Autodesk Fusion 360 part; units mm, degrees
(part 2 of 7)
sketch "Stack support spoke (5)" plane through (0, 0, -6) normal (0, 0, 1) x (1, 0, 0) in component "CORE | PowerShelf"
  line L0 (25.9628, -19.0311) -> (26.8069, -19.3807)
  line L1 (26.8069, -19.3807) -> (27.7128, -19.5)
  line L2 (27.7128, -19.5) -> (28.6187, -19.3807)
  line L3 (28.6187, -19.3807) -> (29.4628, -19.0311)
  line L4 (29.4628, -19.0311) -> (30.1877, -18.4749)
  line L5 (30.1877, -18.4749) -> (30.7439, -17.75)
  line L6 (30.7439, -17.75) -> (31.0936, -16.9059)
  line L7 (31.0936, -16.9059) -> (31.2128, -16)
  line L8 (31.2128, -16) -> (31.0936, -15.0941)
  line L9 (31.0936, -15.0941) -> (30.7439, -14.25)
  line L10 (30.7439, -14.25) -> (30.1877, -13.5251)
  line L11 (30.1877, -13.5251) -> (29.4628, -12.9689)
  line L12 (29.4628, -12.9689) -> (1.75, 3.0311)
  line L13 (1.75, 3.0311) -> (0.9059, 3.3807)
  line L14 (0.9059, 3.3807) -> (0, 3.5)
  line L15 (0, 3.5) -> (-0.9059, 3.3807)
  line L16 (-0.9059, 3.3807) -> (-1.75, 3.0311)
  line L17 (-1.75, 3.0311) -> (-2.4749, 2.4749)
  line L18 (-2.4749, 2.4749) -> (-3.0311, 1.75)
  line L19 (-3.0311, 1.75) -> (-3.3807, 0.9059)
  line L20 (-3.3807, 0.9059) -> (-3.5, 0)
  line L21 (-3.5, 0) -> (-3.3807, -0.9059)
  line L22 (-3.3807, -0.9059) -> (-3.0311, -1.75)
  line L23 (-3.0311, -1.75) -> (-2.4749, -2.4749)
  line L24 (-2.4749, -2.4749) -> (-1.75, -3.0311)
  line L25 (-1.75, -3.0311) -> (25.9628, -19.0311)
extrude "Stack support spoke (6)" add sketch "Stack support spoke (5)" along normal blind 3 bodies 3 in component "CORE | PowerShelf"
ref_plane "WorkPlane8" through (0, 0, -6) normal (0, 0, 1) x (1, 0, 0) in component "CORE | PowerShelf"
sketch "Cooling and M3 stack through holes" plane through (0, 0, -6) normal (0, 0, 1) x (1, 0, 0) in component "CORE | PowerShelf"
  line L0 (7, -16.4) -> (7.3623, -16.3523)
  line L1 (7.3623, -16.3523) -> (7.7, -16.2124)
  line L2 (7.7, -16.2124) -> (7.9899, -15.9899)
  line L3 (7.9899, -15.9899) -> (8.2124, -15.7)
  line L4 (8.2124, -15.7) -> (8.3523, -15.3623)
  line L5 (8.3523, -15.3623) -> (8.4, -15)
  line L6 (8.4, -15) -> (8.3523, -14.6377)
  line L7 (8.3523, -14.6377) -> (8.2124, -14.3)
  line L8 (8.2124, -14.3) -> (7.9899, -14.0101)
  line L9 (7.9899, -14.0101) -> (7.7, -13.7876)
  line L10 (7.7, -13.7876) -> (7.3623, -13.6477)
  line L11 (7.3623, -13.6477) -> (7, -13.6)
  line L12 (7, -13.6) -> (-7, -13.6)
  line L13 (-7, -13.6) -> (-7.3623, -13.6477)
  line L14 (-7.3623, -13.6477) -> (-7.7, -13.7876)
  line L15 (-7.7, -13.7876) -> (-7.9899, -14.0101)
  line L16 (-7.9899, -14.0101) -> (-8.2124, -14.3)
  line L17 (-8.2124, -14.3) -> (-8.3523, -14.6377)
  line L18 (-8.3523, -14.6377) -> (-8.4, -15)
  line L19 (-8.4, -15) -> (-8.3523, -15.3623)
  line L20 (-8.3523, -15.3623) -> (-8.2124, -15.7)
  line L21 (-8.2124, -15.7) -> (-7.9899, -15.9899)
  line L22 (-7.9899, -15.9899) -> (-7.7, -16.2124)
  line L23 (-7.7, -16.2124) -> (-7.3623, -16.3523)
  line L24 (-7.3623, -16.3523) -> (-7, -16.4)
  line L25 (-7, -16.4) -> (7, -16.4)
  line L26 (7, -9.4) -> (7.3623, -9.3523)
  line L27 (7.3623, -9.3523) -> (7.7, -9.2124)
  line L28 (7.7, -9.2124) -> (7.9899, -8.9899)
  line L29 (7.9899, -8.9899) -> (8.2124, -8.7)
  line L30 (8.2124, -8.7) -> (8.3523, -8.3623)
  line L31 (8.3523, -8.3623) -> (8.4, -8)
  line L32 (8.4, -8) -> (8.3523, -7.6377)
  line L33 (8.3523, -7.6377) -> (8.2124, -7.3)
  line L34 (8.2124, -7.3) -> (7.9899, -7.0101)
  line L35 (7.9899, -7.0101) -> (7.7, -6.7876)
  line L36 (7.7, -6.7876) -> (7.3623, -6.6477)
  line L37 (7.3623, -6.6477) -> (7, -6.6)
  line L38 (7, -6.6) -> (-7, -6.6)
  line L39 (-7, -6.6) -> (-7.3623, -6.6477)
  line L40 (-7.3623, -6.6477) -> (-7.7, -6.7876)
  line L41 (-7.7, -6.7876) -> (-7.9899, -7.0101)
  line L42 (-7.9899, -7.0101) -> (-8.2124, -7.3)
  line L43 (-8.2124, -7.3) -> (-8.3523, -7.6377)
  line L44 (-8.3523, -7.6377) -> (-8.4, -8)
  line L45 (-8.4, -8) -> (-8.3523, -8.3623)
  line L46 (-8.3523, -8.3623) -> (-8.2124, -8.7)
  line L47 (-8.2124, -8.7) -> (-7.9899, -8.9899)
  line L48 (-7.9899, -8.9899) -> (-7.7, -9.2124)
  line L49 (-7.7, -9.2124) -> (-7.3623, -9.3523)
  line L50 (-7.3623, -9.3523) -> (-7, -9.4)
  line L51 (-7, -9.4) -> (7, -9.4)
  line L52 (7, -1.4) -> (7.3623, -1.3523)
  line L53 (7.3623, -1.3523) -> (7.7, -1.2124)
  line L54 (7.7, -1.2124) -> (7.9899, -0.9899)
  line L55 (7.9899, -0.9899) -> (8.2124, -0.7)
  line L56 (8.2124, -0.7) -> (8.3523, -0.3623)
  line L57 (8.3523, -0.3623) -> (8.4, 0)
  line L58 (8.4, 0) -> (8.3523, 0.3623)
  line L59 (8.3523, 0.3623) -> (8.2124, 0.7)
  line L60 (8.2124, 0.7) -> (7.9899, 0.9899)
  line L61 (7.9899, 0.9899) -> (7.7, 1.2124)
  line L62 (7.7, 1.2124) -> (7.3623, 1.3523)
  line L63 (7.3623, 1.3523) -> (7, 1.4)
  line L64 (7, 1.4) -> (-7, 1.4)
  line L65 (-7, 1.4) -> (-7.3623, 1.3523)
  line L66 (-7.3623, 1.3523) -> (-7.7, 1.2124)
  line L67 (-7.7, 1.2124) -> (-7.9899, 0.9899)
  line L68 (-7.9899, 0.9899) -> (-8.2124, 0.7)
  line L69 (-8.2124, 0.7) -> (-8.3523, 0.3623)
  line L70 (-8.3523, 0.3623) -> (-8.4, 0)
  line L71 (-8.4, 0) -> (-8.3523, -0.3623)
  line L72 (-8.3523, -0.3623) -> (-8.2124, -0.7)
  line L73 (-8.2124, -0.7) -> (-7.9899, -0.9899)
  line L74 (-7.9899, -0.9899) -> (-7.7, -1.2124)
  line L75 (-7.7, -1.2124) -> (-7.3623, -1.3523)
  line L76 (-7.3623, -1.3523) -> (-7, -1.4)
  line L77 (-7, -1.4) -> (7, -1.4)
  line L78 (7, 6.6) -> (7.3623, 6.6477)
  line L79 (7.3623, 6.6477) -> (7.7, 6.7876)
  line L80 (7.7, 6.7876) -> (7.9899, 7.0101)
  line L81 (7.9899, 7.0101) -> (8.2124, 7.3)
  line L82 (8.2124, 7.3) -> (8.3523, 7.6377)
  line L83 (8.3523, 7.6377) -> (8.4, 8)
  line L84 (8.4, 8) -> (8.3523, 8.3623)
  line L85 (8.3523, 8.3623) -> (8.2124, 8.7)
  line L86 (8.2124, 8.7) -> (7.9899, 8.9899)
  line L87 (7.9899, 8.9899) -> (7.7, 9.2124)
  line L88 (7.7, 9.2124) -> (7.3623, 9.3523)
  line L89 (7.3623, 9.3523) -> (7, 9.4)
  line L90 (7, 9.4) -> (-7, 9.4)
  line L91 (-7, 9.4) -> (-7.3623, 9.3523)
  line L92 (-7.3623, 9.3523) -> (-7.7, 9.2124)
  line L93 (-7.7, 9.2124) -> (-7.9899, 8.9899)
  line L94 (-7.9899, 8.9899) -> (-8.2124, 8.7)
  line L95 (-8.2124, 8.7) -> (-8.3523, 8.3623)
  line L96 (-8.3523, 8.3623) -> (-8.4, 8)
  line L97 (-8.4, 8) -> (-8.3523, 7.6377)
  line L98 (-8.3523, 7.6377) -> (-8.2124, 7.3)
  line L99 (-8.2124, 7.3) -> (-7.9899, 7.0101)
  line L100 (-7.9899, 7.0101) -> (-7.7, 6.7876)
  line L101 (-7.7, 6.7876) -> (-7.3623, 6.6477)
  line L102 (-7.3623, 6.6477) -> (-7, 6.6)
  line L103 (-7, 6.6) -> (7, 6.6)
  line L104 (7, 13.6) -> (7.3623, 13.6477)
  line L105 (7.3623, 13.6477) -> (7.7, 13.7876)
  line L106 (7.7, 13.7876) -> (7.9899, 14.0101)
  line L107 (7.9899, 14.0101) -> (8.2124, 14.3)
  line L108 (8.2124, 14.3) -> (8.3523, 14.6377)
  line L109 (8.3523, 14.6377) -> (8.4, 15)
  line L110 (8.4, 15) -> (8.3523, 15.3623)
  line L111 (8.3523, 15.3623) -> (8.2124, 15.7)
  line L112 (8.2124, 15.7) -> (7.9899, 15.9899)
  line L113 (7.9899, 15.9899) -> (7.7, 16.2124)
  line L114 (7.7, 16.2124) -> (7.3623, 16.3523)
  line L115 (7.3623, 16.3523) -> (7, 16.4)
  line L116 (7, 16.4) -> (-7, 16.4)
  line L117 (-7, 16.4) -> (-7.3623, 16.3523)
  line L118 (-7.3623, 16.3523) -> (-7.7, 16.2124)
  line L119 (-7.7, 16.2124) -> (-7.9899, 15.9899)
  line L120 (-7.9899, 15.9899) -> (-8.2124, 15.7)
  line L121 (-8.2124, 15.7) -> (-8.3523, 15.3623)
  line L122 (-8.3523, 15.3623) -> (-8.4, 15)
  line L123 (-8.4, 15) -> (-8.3523, 14.6377)
  line L124 (-8.3523, 14.6377) -> (-8.2124, 14.3)
  line L125 (-8.2124, 14.3) -> (-7.9899, 14.0101)
  line L126 (-7.9899, 14.0101) -> (-7.7, 13.7876)
  line L127 (-7.7, 13.7876) -> (-7.3623, 13.6477)
  line L128 (-7.3623, 13.6477) -> (-7, 13.6)
  line L129 (-7, 13.6) -> (7, 13.6)
  circle A0 centre (27.7128, 16) radius 1.7
  circle A1 centre (0, 32) radius 1.7
  circle A2 centre (-27.7128, 16) radius 1.7
  circle A3 centre (-27.7128, -16) radius 1.7
  circle A4 centre (0, -32) radius 1.7
  circle A5 centre (27.7128, -16) radius 1.7
extrude "Cooling and M3 stack through holes (1)" cut sketch "Cooling and M3 stack through holes" along normal blind 3 bodies 3 in component "CORE | PowerShelf"
ref_plane "WorkPlane9" through (0, 0, -3) normal (0, 0, 1) x (1, 0, 0) in component "CORE | PowerShelf"
sketch "M2 regulator standoff" plane through (0, 0, -3) normal (0, 0, 1) x (1, 0, 0) in component "CORE | PowerShelf"
  circle A0 centre (-13.716, -19.431) radius 2.8
extrude "M2 regulator standoff (1)" add sketch "M2 regulator standoff" along normal blind 2 bodies 3 in component "CORE | PowerShelf"
ref_plane "WorkPlane10" through (0, 0, -3) normal (0, 0, 1) x (1, 0, 0) in component "CORE | PowerShelf"
sketch "M2 regulator standoff (1)" plane through (0, 0, -3) normal (0, 0, 1) x (1, 0, 0) in component "CORE | PowerShelf"
  circle A0 centre (11.684, -19.431) radius 2.8
extrude "M2 regulator standoff (2)" add sketch "M2 regulator standoff (1)" along normal blind 2 bodies 3 in component "CORE | PowerShelf"
ref_plane "WorkPlane11" through (0, 0, -3) normal (0, 0, 1) x (1, 0, 0) in component "CORE | PowerShelf"
sketch "M2 regulator standoff (2)" plane through (0, 0, -3) normal (0, 0, 1) x (1, 0, 0) in component "CORE | PowerShelf"
  circle A0 centre (-13.716, 19.431) radius 2.8
extrude "M2 regulator standoff (3)" add sketch "M2 regulator standoff (2)" along normal blind 2 bodies 3 in component "CORE | PowerShelf"
ref_plane "WorkPlane12" through (0, 0, -3) normal (0, 0, 1) x (1, 0, 0) in component "CORE | PowerShelf"
sketch "M2 regulator standoff (3)" plane through (0, 0, -3) normal (0, 0, 1) x (1, 0, 0) in component "CORE | PowerShelf"
  circle A0 centre (11.684, 19.431) radius 2.8
extrude "M2 regulator standoff (4)" add sketch "M2 regulator standoff (3)" along normal blind 2 bodies 3 in component "CORE | PowerShelf"
ref_plane "WorkPlane13" through (0, 0, -6) normal (0, 0, 1) x (1, 0, 0) in component "CORE | PowerShelf"
sketch "Pololu D42 exact M2 pattern" plane through (0, 0, -6) normal (0, 0, 1) x (1, 0, 0) in component "CORE | PowerShelf"
  circle A0 centre (-13.716, -19.431) radius 1.2
  circle A1 centre (11.684, -19.431) radius 1.2
  circle A2 centre (-13.716, 19.431) radius 1.2
  circle A3 centre (11.684, 19.431) radius 1.2
extrude "Pololu D42 exact M2 pattern (1)" cut sketch "Pololu D42 exact M2 pattern" along normal blind 5 bodies 3 in component "CORE | PowerShelf"
ref_plane "WorkPlane1" through (0, 0, 12) normal (0, 0, 1) x (1, 0, 0) in component "CORE | ElectronicsDeck"
sketch "PCA open frame" plane through (0, 0, 12) normal (0, 0, 1) x (1, 0, 0) in component "CORE | ElectronicsDeck"
  line L0 (43, 0) -> (42.6321, 5.7432)
  line L1 (42.6321, 5.7432) -> (41.5348, 11.388)
  line L2 (41.5348, 11.388) -> (39.7268, 16.8381)
  line L3 (39.7268, 16.8381) -> (37.2391, 22)
  line L4 (37.2391, 22) -> (34.1142, 26.7855)
  line L5 (34.1142, 26.7855) -> (30.4056, 31.1127)
  line L6 (30.4056, 31.1127) -> (26.1767, 34.9075)
  line L7 (26.1767, 34.9075) -> (21.5, 38.1051)
  line L8 (21.5, 38.1051) -> (16.4554, 40.6507)
  line L9 (16.4554, 40.6507) -> (11.1292, 42.5007)
  line L10 (11.1292, 42.5007) -> (5.6126, 43.6236)
  line L11 (5.6126, 43.6236) -> (0, 44)
  line L12 (0, 44) -> (-5.6126, 43.6236)
  line L13 (-5.6126, 43.6236) -> (-11.1292, 42.5007)
  line L14 (-11.1292, 42.5007) -> (-16.4554, 40.6507)
  line L15 (-16.4554, 40.6507) -> (-21.5, 38.1051)
  line L16 (-21.5, 38.1051) -> (-26.1767, 34.9075)
  line L17 (-26.1767, 34.9075) -> (-30.4056, 31.1127)
  line L18 (-30.4056, 31.1127) -> (-34.1142, 26.7855)
  line L19 (-34.1142, 26.7855) -> (-37.2391, 22)
  line L20 (-37.2391, 22) -> (-39.7268, 16.8381)
  line L21 (-39.7268, 16.8381) -> (-41.5348, 11.388)
  line L22 (-41.5348, 11.388) -> (-42.6321, 5.7432)
  line L23 (-42.6321, 5.7432) -> (-43, 0)
  line L24 (-43, 0) -> (-42.6321, -5.7432)
  line L25 (-42.6321, -5.7432) -> (-41.5348, -11.388)
  line L26 (-41.5348, -11.388) -> (-39.7268, -16.8381)
  line L27 (-39.7268, -16.8381) -> (-37.2391, -22)
  line L28 (-37.2391, -22) -> (-34.1142, -26.7855)
  line L29 (-34.1142, -26.7855) -> (-30.4056, -31.1127)
  line L30 (-30.4056, -31.1127) -> (-26.1767, -34.9075)
  line L31 (-26.1767, -34.9075) -> (-21.5, -38.1051)
  line L32 (-21.5, -38.1051) -> (-16.4554, -40.6507)
  line L33 (-16.4554, -40.6507) -> (-11.1292, -42.5007)
  line L34 (-11.1292, -42.5007) -> (-5.6126, -43.6236)
  line L35 (-5.6126, -43.6236) -> (0, -44)
  line L36 (0, -44) -> (5.6126, -43.6236)
  line L37 (5.6126, -43.6236) -> (11.1292, -42.5007)
  line L38 (11.1292, -42.5007) -> (16.4554, -40.6507)
  line L39 (16.4554, -40.6507) -> (21.5, -38.1051)
  line L40 (21.5, -38.1051) -> (26.1767, -34.9075)
  line L41 (26.1767, -34.9075) -> (30.4056, -31.1127)
  line L42 (30.4056, -31.1127) -> (34.1142, -26.7855)
  line L43 (34.1142, -26.7855) -> (37.2391, -22)
  line L44 (37.2391, -22) -> (39.7268, -16.8381)
  line L45 (39.7268, -16.8381) -> (41.5348, -11.388)
  line L46 (41.5348, -11.388) -> (42.6321, -5.7432)
  line L47 (42.6321, -5.7432) -> (43, 0)
extrude "PCA open frame (1)" add sketch "PCA open frame" along normal blind 3 separate body makes body 4 in component "CORE | ElectronicsDeck"
ref_plane "WorkPlane2" through (0, 0, 12) normal (0, 0, 1) x (1, 0, 0) in component "CORE | ElectronicsDeck"
sketch "Core open cooling aperture" plane through (0, 0, 12) normal (0, 0, 1) x (1, 0, 0) in component "CORE | ElectronicsDeck"
  line L0 (35, 0) -> (34.7006, 4.6989)
  line L1 (34.7006, 4.6989) -> (33.8074, 9.3175)
  line L2 (33.8074, 9.3175) -> (32.3358, 13.7766)
  line L3 (32.3358, 13.7766) -> (30.3109, 18)
  line L4 (30.3109, 18) -> (27.7674, 21.9154)
  line L5 (27.7674, 21.9154) -> (24.7487, 25.4558)
  line L6 (24.7487, 25.4558) -> (21.3067, 28.5607)
  line L7 (21.3067, 28.5607) -> (17.5, 31.1769)
  line L8 (17.5, 31.1769) -> (13.3939, 33.2597)
  line L9 (13.3939, 33.2597) -> (9.0587, 34.7733)
  line L10 (9.0587, 34.7733) -> (4.5684, 35.692)
  line L11 (4.5684, 35.692) -> (0, 36)
  line L12 (0, 36) -> (-4.5684, 35.692)
  line L13 (-4.5684, 35.692) -> (-9.0587, 34.7733)
  line L14 (-9.0587, 34.7733) -> (-13.3939, 33.2597)
  line L15 (-13.3939, 33.2597) -> (-17.5, 31.1769)
  line L16 (-17.5, 31.1769) -> (-21.3067, 28.5607)
  line L17 (-21.3067, 28.5607) -> (-24.7487, 25.4558)
  line L18 (-24.7487, 25.4558) -> (-27.7674, 21.9154)
  line L19 (-27.7674, 21.9154) -> (-30.3109, 18)
  line L20 (-30.3109, 18) -> (-32.3358, 13.7766)
  line L21 (-32.3358, 13.7766) -> (-33.8074, 9.3175)
  line L22 (-33.8074, 9.3175) -> (-34.7006, 4.6989)
  line L23 (-34.7006, 4.6989) -> (-35, 0)
  line L24 (-35, 0) -> (-34.7006, -4.6989)
  line L25 (-34.7006, -4.6989) -> (-33.8074, -9.3175)
  line L26 (-33.8074, -9.3175) -> (-32.3358, -13.7766)
  line L27 (-32.3358, -13.7766) -> (-30.3109, -18)
  line L28 (-30.3109, -18) -> (-27.7674, -21.9154)
  line L29 (-27.7674, -21.9154) -> (-24.7487, -25.4558)
  line L30 (-24.7487, -25.4558) -> (-21.3067, -28.5607)
  line L31 (-21.3067, -28.5607) -> (-17.5, -31.1769)
  line L32 (-17.5, -31.1769) -> (-13.3939, -33.2597)
  line L33 (-13.3939, -33.2597) -> (-9.0587, -34.7733)
  line L34 (-9.0587, -34.7733) -> (-4.5684, -35.692)
  line L35 (-4.5684, -35.692) -> (0, -36)
  line L36 (0, -36) -> (4.5684, -35.692)
  line L37 (4.5684, -35.692) -> (9.0587, -34.7733)
  line L38 (9.0587, -34.7733) -> (13.3939, -33.2597)
  line L39 (13.3939, -33.2597) -> (17.5, -31.1769)
  line L40 (17.5, -31.1769) -> (21.3067, -28.5607)
  line L41 (21.3067, -28.5607) -> (24.7487, -25.4558)
  line L42 (24.7487, -25.4558) -> (27.7674, -21.9154)
  line L43 (27.7674, -21.9154) -> (30.3109, -18)
  line L44 (30.3109, -18) -> (32.3358, -13.7766)
  line L45 (32.3358, -13.7766) -> (33.8074, -9.3175)
  line L46 (33.8074, -9.3175) -> (34.7006, -4.6989)
  line L47 (34.7006, -4.6989) -> (35, 0)
extrude "Core open cooling aperture (1)" cut sketch "Core open cooling aperture" along normal blind 3 bodies 4 in component "CORE | ElectronicsDeck"
ref_plane "WorkPlane3" through (0, 0, 12) normal (0, 0, 1) x (1, 0, 0) in component "CORE | ElectronicsDeck"
sketch "PCA mount radial bridge" plane through (0, 0, 12) normal (0, 0, 1) x (1, 0, 0) in component "CORE | ElectronicsDeck"
  line L0 (-30.94, -37) -> (-30.8378, -37.7765)
  line L1 (-30.8378, -37.7765) -> (-30.5381, -38.5)
  line L2 (-30.5381, -38.5) -> (-30.0613, -39.1213)
  line L3 (-30.0613, -39.1213) -> (-29.44, -39.5981)
  line L4 (-29.44, -39.5981) -> (-28.7165, -39.8978)
  line L5 (-28.7165, -39.8978) -> (-27.94, -40)
  line L6 (-27.94, -40) -> (-27.1635, -39.8978)
  line L7 (-27.1635, -39.8978) -> (-26.44, -39.5981)
  line L8 (-26.44, -39.5981) -> (-25.8187, -39.1213)
  line L9 (-25.8187, -39.1213) -> (-25.3419, -38.5)
  line L10 (-25.3419, -38.5) -> (-25.0422, -37.7765)
  line L11 (-25.0422, -37.7765) -> (-24.94, -37)
  line L12 (-24.94, -37) -> (-24.94, -25.525)
  line L13 (-24.94, -25.525) -> (-25.0422, -24.7485)
  line L14 (-25.0422, -24.7485) -> (-25.3419, -24.025)
  line L15 (-25.3419, -24.025) -> (-25.8187, -23.4037)
  line L16 (-25.8187, -23.4037) -> (-26.44, -22.9269)
  line L17 (-26.44, -22.9269) -> (-27.1635, -22.6272)
  line L18 (-27.1635, -22.6272) -> (-27.94, -22.525)
  line L19 (-27.94, -22.525) -> (-28.7165, -22.6272)
  line L20 (-28.7165, -22.6272) -> (-29.44, -22.9269)
  line L21 (-29.44, -22.9269) -> (-30.0613, -23.4037)
  line L22 (-30.0613, -23.4037) -> (-30.5381, -24.025)
  line L23 (-30.5381, -24.025) -> (-30.8378, -24.7485)
  line L24 (-30.8378, -24.7485) -> (-30.94, -25.525)
  line L25 (-30.94, -25.525) -> (-30.94, -37)
extrude "PCA mount radial bridge (1)" add sketch "PCA mount radial bridge" along normal blind 3 bodies 4 in component "CORE | ElectronicsDeck"
ref_plane "WorkPlane4" through (0, 0, 15) normal (0, 0, 1) x (1, 0, 0) in component "CORE | ElectronicsDeck"
sketch "PCA insulated M2 standoff" plane through (0, 0, 15) normal (0, 0, 1) x (1, 0, 0) in component "CORE | ElectronicsDeck"
  circle A0 centre (-27.94, -25.525) radius 2.8
extrude "PCA insulated M2 standoff (1)" add sketch "PCA insulated M2 standoff" along normal blind 6 bodies 4 in component "CORE | ElectronicsDeck"
ref_plane "WorkPlane5" through (0, 0, 12) normal (0, 0, 1) x (1, 0, 0) in component "CORE | ElectronicsDeck"
sketch "PCA mount radial bridge (1)" plane through (0, 0, 12) normal (0, 0, 1) x (1, 0, 0) in component "CORE | ElectronicsDeck"
  line L0 (-30.94, -37) -> (-30.8378, -37.7765)
  line L1 (-30.8378, -37.7765) -> (-30.5381, -38.5)
  line L2 (-30.5381, -38.5) -> (-30.0613, -39.1213)
  line L3 (-30.0613, -39.1213) -> (-29.44, -39.5981)
  line L4 (-29.44, -39.5981) -> (-28.7165, -39.8978)
  line L5 (-28.7165, -39.8978) -> (-27.94, -40)
  line L6 (-27.94, -40) -> (-27.1635, -39.8978)
  line L7 (-27.1635, -39.8978) -> (-26.44, -39.5981)
  line L8 (-26.44, -39.5981) -> (-25.8187, -39.1213)
  line L9 (-25.8187, -39.1213) -> (-25.3419, -38.5)
  line L10 (-25.3419, -38.5) -> (-25.0422, -37.7765)
  line L11 (-25.0422, -37.7765) -> (-24.94, -37)
  line L12 (-24.94, -37) -> (-24.94, -6.475)
  line L13 (-24.94, -6.475) -> (-25.0422, -5.6985)
  line L14 (-25.0422, -5.6985) -> (-25.3419, -4.975)
  line L15 (-25.3419, -4.975) -> (-25.8187, -4.3537)
  line L16 (-25.8187, -4.3537) -> (-26.44, -3.8769)
  line L17 (-26.44, -3.8769) -> (-27.1635, -3.5772)
  line L18 (-27.1635, -3.5772) -> (-27.94, -3.475)
  line L19 (-27.94, -3.475) -> (-28.7165, -3.5772)
  line L20 (-28.7165, -3.5772) -> (-29.44, -3.8769)
  line L21 (-29.44, -3.8769) -> (-30.0613, -4.3537)
  line L22 (-30.0613, -4.3537) -> (-30.5381, -4.975)
  line L23 (-30.5381, -4.975) -> (-30.8378, -5.6985)
  line L24 (-30.8378, -5.6985) -> (-30.94, -6.475)
  line L25 (-30.94, -6.475) -> (-30.94, -37)
extrude "PCA mount radial bridge (2)" add sketch "PCA mount radial bridge (1)" along normal blind 3 bodies 4 in component "CORE | ElectronicsDeck"
ref_plane "WorkPlane6" through (0, 0, 15) normal (0, 0, 1) x (1, 0, 0) in component "CORE | ElectronicsDeck"
sketch "PCA insulated M2 standoff (1)" plane through (0, 0, 15) normal (0, 0, 1) x (1, 0, 0) in component "CORE | ElectronicsDeck"
  circle A0 centre (-27.94, -6.475) radius 2.8
extrude "PCA insulated M2 standoff (2)" add sketch "PCA insulated M2 standoff (1)" along normal blind 6 bodies 4 in component "CORE | ElectronicsDeck"
ref_plane "WorkPlane7" through (0, 0, 12) normal (0, 0, 1) x (1, 0, 0) in component "CORE | ElectronicsDeck"
sketch "PCA mount radial bridge (2)" plane through (0, 0, 12) normal (0, 0, 1) x (1, 0, 0) in component "CORE | ElectronicsDeck"
  line L0 (24.94, -37) -> (25.0422, -37.7765)
  line L1 (25.0422, -37.7765) -> (25.3419, -38.5)
  line L2 (25.3419, -38.5) -> (25.8187, -39.1213)
  line L3 (25.8187, -39.1213) -> (26.44, -39.5981)
  line L4 (26.44, -39.5981) -> (27.1635, -39.8978)
  line L5 (27.1635, -39.8978) -> (27.94, -40)
  line L6 (27.94, -40) -> (28.7165, -39.8978)
  line L7 (28.7165, -39.8978) -> (29.44, -39.5981)
  line L8 (29.44, -39.5981) -> (30.0613, -39.1213)
  line L9 (30.0613, -39.1213) -> (30.5381, -38.5)
  line L10 (30.5381, -38.5) -> (30.8378, -37.7765)
  line L11 (30.8378, -37.7765) -> (30.94, -37)
  line L12 (30.94, -37) -> (30.94, -25.525)
  line L13 (30.94, -25.525) -> (30.8378, -24.7485)
  line L14 (30.8378, -24.7485) -> (30.5381, -24.025)
  line L15 (30.5381, -24.025) -> (30.0613, -23.4037)
  line L16 (30.0613, -23.4037) -> (29.44, -22.9269)
  line L17 (29.44, -22.9269) -> (28.7165, -22.6272)
  line L18 (28.7165, -22.6272) -> (27.94, -22.525)
  line L19 (27.94, -22.525) -> (27.1635, -22.6272)
  line L20 (27.1635, -22.6272) -> (26.44, -22.9269)
  line L21 (26.44, -22.9269) -> (25.8187, -23.4037)
  line L22 (25.8187, -23.4037) -> (25.3419, -24.025)
  line L23 (25.3419, -24.025) -> (25.0422, -24.7485)
  line L24 (25.0422, -24.7485) -> (24.94, -25.525)
  line L25 (24.94, -25.525) -> (24.94, -37)
extrude "PCA mount radial bridge (3)" add sketch "PCA mount radial bridge (2)" along normal blind 3 bodies 4 in component "CORE | ElectronicsDeck"
ref_plane "WorkPlane8" through (0, 0, 15) normal (0, 0, 1) x (1, 0, 0) in component "CORE | ElectronicsDeck"
sketch "PCA insulated M2 standoff (2)" plane through (0, 0, 15) normal (0, 0, 1) x (1, 0, 0) in component "CORE | ElectronicsDeck"
  circle A0 centre (27.94, -25.525) radius 2.8
extrude "PCA insulated M2 standoff (3)" add sketch "PCA insulated M2 standoff (2)" along normal blind 6 bodies 4 in component "CORE | ElectronicsDeck"
ref_plane "WorkPlane9" through (0, 0, 12) normal (0, 0, 1) x (1, 0, 0) in component "CORE | ElectronicsDeck"
sketch "PCA mount radial bridge (3)" plane through (0, 0, 12) normal (0, 0, 1) x (1, 0, 0) in component "CORE | ElectronicsDeck"
  line L0 (24.94, -37) -> (25.0422, -37.7765)
  line L1 (25.0422, -37.7765) -> (25.3419, -38.5)
  line L2 (25.3419, -38.5) -> (25.8187, -39.1213)
  line L3 (25.8187, -39.1213) -> (26.44, -39.5981)
  line L4 (26.44, -39.5981) -> (27.1635, -39.8978)
  line L5 (27.1635, -39.8978) -> (27.94, -40)
  line L6 (27.94, -40) -> (28.7165, -39.8978)
  line L7 (28.7165, -39.8978) -> (29.44, -39.5981)
  line L8 (29.44, -39.5981) -> (30.0613, -39.1213)
  line L9 (30.0613, -39.1213) -> (30.5381, -38.5)
  line L10 (30.5381, -38.5) -> (30.8378, -37.7765)
  line L11 (30.8378, -37.7765) -> (30.94, -37)
  line L12 (30.94, -37) -> (30.94, -6.475)
  line L13 (30.94, -6.475) -> (30.8378, -5.6985)
  line L14 (30.8378, -5.6985) -> (30.5381, -4.975)
  line L15 (30.5381, -4.975) -> (30.0613, -4.3537)
  line L16 (30.0613, -4.3537) -> (29.44, -3.8769)
  line L17 (29.44, -3.8769) -> (28.7165, -3.5772)
  line L18 (28.7165, -3.5772) -> (27.94, -3.475)
  line L19 (27.94, -3.475) -> (27.1635, -3.5772)
  line L20 (27.1635, -3.5772) -> (26.44, -3.8769)
  line L21 (26.44, -3.8769) -> (25.8187, -4.3537)
  line L22 (25.8187, -4.3537) -> (25.3419, -4.975)
  line L23 (25.3419, -4.975) -> (25.0422, -5.6985)
  line L24 (25.0422, -5.6985) -> (24.94, -6.475)
  line L25 (24.94, -6.475) -> (24.94, -37)
extrude "PCA mount radial bridge (4)" add sketch "PCA mount radial bridge (3)" along normal blind 3 bodies 4 in component "CORE | ElectronicsDeck"
ref_plane "WorkPlane10" through (0, 0, 15) normal (0, 0, 1) x (1, 0, 0) in component "CORE | ElectronicsDeck"
sketch "PCA insulated M2 standoff (3)" plane through (0, 0, 15) normal (0, 0, 1) x (1, 0, 0) in component "CORE | ElectronicsDeck"
  circle A0 centre (27.94, -6.475) radius 2.8
extrude "PCA insulated M2 standoff (4)" add sketch "PCA insulated M2 standoff (3)" along normal blind 6 bodies 4 in component "CORE | ElectronicsDeck"
ref_plane "WorkPlane11" through (0, 0, 12) normal (0, 0, 1) x (1, 0, 0) in component "CORE | ElectronicsDeck"
sketch "PCA mount radial bridge (4)" plane through (0, 0, 12) normal (0, 0, 1) x (1, 0, 0) in component "CORE | ElectronicsDeck"
  line L0 (30.94, 37) -> (30.8378, 37.7765)
  line L1 (30.8378, 37.7765) -> (30.5381, 38.5)
  line L2 (30.5381, 38.5) -> (30.0613, 39.1213)
  line L3 (30.0613, 39.1213) -> (29.44, 39.5981)
  line L4 (29.44, 39.5981) -> (28.7165, 39.8978)
  line L5 (28.7165, 39.8978) -> (27.94, 40)
  line L6 (27.94, 40) -> (27.1635, 39.8978)
  line L7 (27.1635, 39.8978) -> (26.44, 39.5981)
  line L8 (26.44, 39.5981) -> (25.8187, 39.1213)
  line L9 (25.8187, 39.1213) -> (25.3419, 38.5)
  line L10 (25.3419, 38.5) -> (25.0422, 37.7765)
  line L11 (25.0422, 37.7765) -> (24.94, 37)
  line L12 (24.94, 37) -> (24.94, 25.525)
  line L13 (24.94, 25.525) -> (25.0422, 24.7485)
  line L14 (25.0422, 24.7485) -> (25.3419, 24.025)
  line L15 (25.3419, 24.025) -> (25.8187, 23.4037)
  line L16 (25.8187, 23.4037) -> (26.44, 22.9269)
  line L17 (26.44, 22.9269) -> (27.1635, 22.6272)
  line L18 (27.1635, 22.6272) -> (27.94, 22.525)
  line L19 (27.94, 22.525) -> (28.7165, 22.6272)
  line L20 (28.7165, 22.6272) -> (29.44, 22.9269)
  line L21 (29.44, 22.9269) -> (30.0613, 23.4037)
  line L22 (30.0613, 23.4037) -> (30.5381, 24.025)
  line L23 (30.5381, 24.025) -> (30.8378, 24.7485)
  line L24 (30.8378, 24.7485) -> (30.94, 25.525)
  line L25 (30.94, 25.525) -> (30.94, 37)
extrude "PCA mount radial bridge (5)" add sketch "PCA mount radial bridge (4)" along normal blind 3 bodies 4 in component "CORE | ElectronicsDeck"
ref_plane "WorkPlane12" through (0, 0, 15) normal (0, 0, 1) x (1, 0, 0) in component "CORE | ElectronicsDeck"
sketch "PCA insulated M2 standoff (4)" plane through (0, 0, 15) normal (0, 0, 1) x (1, 0, 0) in component "CORE | ElectronicsDeck"
  circle A0 centre (27.94, 25.525) radius 2.8
extrude "PCA insulated M2 standoff (5)" add sketch "PCA insulated M2 standoff (4)" along normal blind 6 bodies 4 in component "CORE | ElectronicsDeck"
ref_plane "WorkPlane13" through (0, 0, 12) normal (0, 0, 1) x (1, 0, 0) in component "CORE | ElectronicsDeck"
sketch "PCA mount radial bridge (5)" plane through (0, 0, 12) normal (0, 0, 1) x (1, 0, 0) in component "CORE | ElectronicsDeck"
  line L0 (30.94, 37) -> (30.8378, 37.7765)
  line L1 (30.8378, 37.7765) -> (30.5381, 38.5)
  line L2 (30.5381, 38.5) -> (30.0613, 39.1213)
  line L3 (30.0613, 39.1213) -> (29.44, 39.5981)
  line L4 (29.44, 39.5981) -> (28.7165, 39.8978)
  line L5 (28.7165, 39.8978) -> (27.94, 40)
  line L6 (27.94, 40) -> (27.1635, 39.8978)
  line L7 (27.1635, 39.8978) -> (26.44, 39.5981)
  line L8 (26.44, 39.5981) -> (25.8187, 39.1213)
  line L9 (25.8187, 39.1213) -> (25.3419, 38.5)
  line L10 (25.3419, 38.5) -> (25.0422, 37.7765)
  line L11 (25.0422, 37.7765) -> (24.94, 37)
  line L12 (24.94, 37) -> (24.94, 6.475)
  line L13 (24.94, 6.475) -> (25.0422, 5.6985)
  line L14 (25.0422, 5.6985) -> (25.3419, 4.975)
  line L15 (25.3419, 4.975) -> (25.8187, 4.3537)
  line L16 (25.8187, 4.3537) -> (26.44, 3.8769)
  line L17 (26.44, 3.8769) -> (27.1635, 3.5772)
  line L18 (27.1635, 3.5772) -> (27.94, 3.475)
  line L19 (27.94, 3.475) -> (28.7165, 3.5772)
  line L20 (28.7165, 3.5772) -> (29.44, 3.8769)
  line L21 (29.44, 3.8769) -> (30.0613, 4.3537)
  line L22 (30.0613, 4.3537) -> (30.5381, 4.975)
  line L23 (30.5381, 4.975) -> (30.8378, 5.6985)
  line L24 (30.8378, 5.6985) -> (30.94, 6.475)
  line L25 (30.94, 6.475) -> (30.94, 37)
extrude "PCA mount radial bridge (6)" add sketch "PCA mount radial bridge (5)" along normal blind 3 bodies 4 in component "CORE | ElectronicsDeck"
ref_plane "WorkPlane14" through (0, 0, 15) normal (0, 0, 1) x (1, 0, 0) in component "CORE | ElectronicsDeck"
sketch "PCA insulated M2 standoff (5)" plane through (0, 0, 15) normal (0, 0, 1) x (1, 0, 0) in component "CORE | ElectronicsDeck"
  circle A0 centre (27.94, 6.475) radius 2.8
extrude "PCA insulated M2 standoff (6)" add sketch "PCA insulated M2 standoff (5)" along normal blind 6 bodies 4 in component "CORE | ElectronicsDeck"
ref_plane "WorkPlane15" through (0, 0, 12) normal (0, 0, 1) x (1, 0, 0) in component "CORE | ElectronicsDeck"
sketch "PCA mount radial bridge (6)" plane through (0, 0, 12) normal (0, 0, 1) x (1, 0, 0) in component "CORE | ElectronicsDeck"
  line L0 (-24.94, 37) -> (-25.0422, 37.7765)
  line L1 (-25.0422, 37.7765) -> (-25.3419, 38.5)
  line L2 (-25.3419, 38.5) -> (-25.8187, 39.1213)
  line L3 (-25.8187, 39.1213) -> (-26.44, 39.5981)
  line L4 (-26.44, 39.5981) -> (-27.1635, 39.8978)
  line L5 (-27.1635, 39.8978) -> (-27.94, 40)
  line L6 (-27.94, 40) -> (-28.7165, 39.8978)
  line L7 (-28.7165, 39.8978) -> (-29.44, 39.5981)
  line L8 (-29.44, 39.5981) -> (-30.0613, 39.1213)
  line L9 (-30.0613, 39.1213) -> (-30.5381, 38.5)
  line L10 (-30.5381, 38.5) -> (-30.8378, 37.7765)
  line L11 (-30.8378, 37.7765) -> (-30.94, 37)
  line L12 (-30.94, 37) -> (-30.94, 25.525)
  line L13 (-30.94, 25.525) -> (-30.8378, 24.7485)
  line L14 (-30.8378, 24.7485) -> (-30.5381, 24.025)
  line L15 (-30.5381, 24.025) -> (-30.0613, 23.4037)
  line L16 (-30.0613, 23.4037) -> (-29.44, 22.9269)
  line L17 (-29.44, 22.9269) -> (-28.7165, 22.6272)
  line L18 (-28.7165, 22.6272) -> (-27.94, 22.525)
  line L19 (-27.94, 22.525) -> (-27.1635, 22.6272)
  line L20 (-27.1635, 22.6272) -> (-26.44, 22.9269)
  line L21 (-26.44, 22.9269) -> (-25.8187, 23.4037)
  line L22 (-25.8187, 23.4037) -> (-25.3419, 24.025)
  line L23 (-25.3419, 24.025) -> (-25.0422, 24.7485)
  line L24 (-25.0422, 24.7485) -> (-24.94, 25.525)
  line L25 (-24.94, 25.525) -> (-24.94, 37)
extrude "PCA mount radial bridge (7)" add sketch "PCA mount radial bridge (6)" along normal blind 3 bodies 4 in component "CORE | ElectronicsDeck"
ref_plane "WorkPlane16" through (0, 0, 15) normal (0, 0, 1) x (1, 0, 0) in component "CORE | ElectronicsDeck"
sketch "PCA insulated M2 standoff (6)" plane through (0, 0, 15) normal (0, 0, 1) x (1, 0, 0) in component "CORE | ElectronicsDeck"
  circle A0 centre (-27.94, 25.525) radius 2.8
extrude "PCA insulated M2 standoff (7)" add sketch "PCA insulated M2 standoff (6)" along normal blind 6 bodies 4 in component "CORE | ElectronicsDeck"
ref_plane "WorkPlane17" through (0, 0, 12) normal (0, 0, 1) x (1, 0, 0) in component "CORE | ElectronicsDeck"
sketch "PCA mount radial bridge (7)" plane through (0, 0, 12) normal (0, 0, 1) x (1, 0, 0) in component "CORE | ElectronicsDeck"
  line L0 (-24.94, 37) -> (-25.0422, 37.7765)
  line L1 (-25.0422, 37.7765) -> (-25.3419, 38.5)
  line L2 (-25.3419, 38.5) -> (-25.8187, 39.1213)
  line L3 (-25.8187, 39.1213) -> (-26.44, 39.5981)
  line L4 (-26.44, 39.5981) -> (-27.1635, 39.8978)
  line L5 (-27.1635, 39.8978) -> (-27.94, 40)
  line L6 (-27.94, 40) -> (-28.7165, 39.8978)
  line L7 (-28.7165, 39.8978) -> (-29.44, 39.5981)
  line L8 (-29.44, 39.5981) -> (-30.0613, 39.1213)
  line L9 (-30.0613, 39.1213) -> (-30.5381, 38.5)
  line L10 (-30.5381, 38.5) -> (-30.8378, 37.7765)
  line L11 (-30.8378, 37.7765) -> (-30.94, 37)
  line L12 (-30.94, 37) -> (-30.94, 6.475)
  line L13 (-30.94, 6.475) -> (-30.8378, 5.6985)
  line L14 (-30.8378, 5.6985) -> (-30.5381, 4.975)
  line L15 (-30.5381, 4.975) -> (-30.0613, 4.3537)
  line L16 (-30.0613, 4.3537) -> (-29.44, 3.8769)
  line L17 (-29.44, 3.8769) -> (-28.7165, 3.5772)
  line L18 (-28.7165, 3.5772) -> (-27.94, 3.475)
  line L19 (-27.94, 3.475) -> (-27.1635, 3.5772)
  line L20 (-27.1635, 3.5772) -> (-26.44, 3.8769)
  line L21 (-26.44, 3.8769) -> (-25.8187, 4.3537)
  line L22 (-25.8187, 4.3537) -> (-25.3419, 4.975)
  line L23 (-25.3419, 4.975) -> (-25.0422, 5.6985)
  line L24 (-25.0422, 5.6985) -> (-24.94, 6.475)
  line L25 (-24.94, 6.475) -> (-24.94, 37)
extrude "PCA mount radial bridge (8)" add sketch "PCA mount radial bridge (7)" along normal blind 3 bodies 4 in component "CORE | ElectronicsDeck"
ref_plane "WorkPlane18" through (0, 0, 15) normal (0, 0, 1) x (1, 0, 0) in component "CORE | ElectronicsDeck"
sketch "PCA insulated M2 standoff (7)" plane through (0, 0, 15) normal (0, 0, 1) x (1, 0, 0) in component "CORE | ElectronicsDeck"
  circle A0 centre (-27.94, 6.475) radius 2.8
extrude "PCA insulated M2 standoff (8)" add sketch "PCA insulated M2 standoff (7)" along normal blind 6 bodies 4 in component "CORE | ElectronicsDeck"
ref_plane "WorkPlane19" through (0, 0, 12) normal (0, 0, 1) x (1, 0, 0) in component "CORE | ElectronicsDeck"
sketch "Stack bolt seat bridge" plane through (0, 0, 12) normal (0, 0, 1) x (1, 0, 0) in component "CORE | ElectronicsDeck"
  line L0 (35.0054, 16.1689) -> (35.7302, 16.7251)
  line L1 (35.7302, 16.7251) -> (36.2865, 17.45)
  line L2 (36.2865, 17.45) -> (36.6361, 18.2941)
  line L3 (36.6361, 18.2941) -> (36.7554, 19.2)
  line L4 (36.7554, 19.2) -> (36.6361, 20.1059)
  line L5 (36.6361, 20.1059) -> (36.2865, 20.95)
  line L6 (36.2865, 20.95) -> (35.7302, 21.6749)
  line L7 (35.7302, 21.6749) -> (35.0054, 22.2311)
  line L8 (35.0054, 22.2311) -> (34.1612, 22.5807)
  line L9 (34.1612, 22.5807) -> (33.2554, 22.7)
  line L10 (33.2554, 22.7) -> (32.3495, 22.5807)
  line L11 (32.3495, 22.5807) -> (31.5054, 22.2311)
  line L12 (31.5054, 22.2311) -> (25.9628, 19.0311)
  line L13 (25.9628, 19.0311) -> (25.2379, 18.4749)
  line L14 (25.2379, 18.4749) -> (24.6817, 17.75)
  line L15 (24.6817, 17.75) -> (24.3321, 16.9059)
  line L16 (24.3321, 16.9059) -> (24.2128, 16)
  line L17 (24.2128, 16) -> (24.3321, 15.0941)
  line L18 (24.3321, 15.0941) -> (24.6817, 14.25)
  line L19 (24.6817, 14.25) -> (25.2379, 13.5251)
  line L20 (25.2379, 13.5251) -> (25.9628, 12.9689)
  line L21 (25.9628, 12.9689) -> (26.8069, 12.6193)
  line L22 (26.8069, 12.6193) -> (27.7128, 12.5)
  line L23 (27.7128, 12.5) -> (28.6187, 12.6193)
  line L24 (28.6187, 12.6193) -> (29.4628, 12.9689)
  line L25 (29.4628, 12.9689) -> (35.0054, 16.1689)
extrude "Stack bolt seat bridge (1)" add sketch "Stack bolt seat bridge" along normal blind 3 bodies 4 in component "CORE | ElectronicsDeck"
ref_plane "WorkPlane20" through (0, 0, 12) normal (0, 0, 1) x (1, 0, 0) in component "CORE | ElectronicsDeck"
sketch "Stack bolt seat bridge (1)" plane through (0, 0, 12) normal (0, 0, 1) x (1, 0, 0) in component "CORE | ElectronicsDeck"
  line L0 (3.5, 38.4) -> (3.3807, 39.3059)
  line L1 (3.3807, 39.3059) -> (3.0311, 40.15)
  line L2 (3.0311, 40.15) -> (2.4749, 40.8749)
  line L3 (2.4749, 40.8749) -> (1.75, 41.4311)
  line L4 (1.75, 41.4311) -> (0.9059, 41.7807)
  line L5 (0.9059, 41.7807) -> (0, 41.9)
  line L6 (0, 41.9) -> (-0.9059, 41.7807)
  line L7 (-0.9059, 41.7807) -> (-1.75, 41.4311)
  line L8 (-1.75, 41.4311) -> (-2.4749, 40.8749)
  line L9 (-2.4749, 40.8749) -> (-3.0311, 40.15)
  line L10 (-3.0311, 40.15) -> (-3.3807, 39.3059)
  line L11 (-3.3807, 39.3059) -> (-3.5, 38.4)
  line L12 (-3.5, 38.4) -> (-3.5, 32)
  line L13 (-3.5, 32) -> (-3.3807, 31.0941)
  line L14 (-3.3807, 31.0941) -> (-3.0311, 30.25)
  line L15 (-3.0311, 30.25) -> (-2.4749, 29.5251)
  line L16 (-2.4749, 29.5251) -> (-1.75, 28.9689)
  line L17 (-1.75, 28.9689) -> (-0.9059, 28.6193)
  line L18 (-0.9059, 28.6193) -> (0, 28.5)
  line L19 (0, 28.5) -> (0.9059, 28.6193)
  line L20 (0.9059, 28.6193) -> (1.75, 28.9689)
  line L21 (1.75, 28.9689) -> (2.4749, 29.5251)
  line L22 (2.4749, 29.5251) -> (3.0311, 30.25)
  line L23 (3.0311, 30.25) -> (3.3807, 31.0941)
  line L24 (3.3807, 31.0941) -> (3.5, 32)
  line L25 (3.5, 32) -> (3.5, 38.4)
extrude "Stack bolt seat bridge (2)" add sketch "Stack bolt seat bridge (1)" along normal blind 3 bodies 4 in component "CORE | ElectronicsDeck"
ref_plane "WorkPlane21" through (0, 0, 12) normal (0, 0, 1) x (1, 0, 0) in component "CORE | ElectronicsDeck"
sketch "Stack bolt seat bridge (2)" plane through (0, 0, 12) normal (0, 0, 1) x (1, 0, 0) in component "CORE | ElectronicsDeck"
  line L0 (-31.5054, 22.2311) -> (-32.3495, 22.5807)
  line L1 (-32.3495, 22.5807) -> (-33.2554, 22.7)
  line L2 (-33.2554, 22.7) -> (-34.1612, 22.5807)
  line L3 (-34.1612, 22.5807) -> (-35.0054, 22.2311)
  line L4 (-35.0054, 22.2311) -> (-35.7302, 21.6749)
  line L5 (-35.7302, 21.6749) -> (-36.2865, 20.95)
  line L6 (-36.2865, 20.95) -> (-36.6361, 20.1059)
  line L7 (-36.6361, 20.1059) -> (-36.7554, 19.2)
  line L8 (-36.7554, 19.2) -> (-36.6361, 18.2941)
  line L9 (-36.6361, 18.2941) -> (-36.2865, 17.45)
  line L10 (-36.2865, 17.45) -> (-35.7302, 16.7251)
  line L11 (-35.7302, 16.7251) -> (-35.0054, 16.1689)
  line L12 (-35.0054, 16.1689) -> (-29.4628, 12.9689)
  line L13 (-29.4628, 12.9689) -> (-28.6187, 12.6193)
  line L14 (-28.6187, 12.6193) -> (-27.7128, 12.5)
  line L15 (-27.7128, 12.5) -> (-26.8069, 12.6193)
  line L16 (-26.8069, 12.6193) -> (-25.9628, 12.9689)
  line L17 (-25.9628, 12.9689) -> (-25.2379, 13.5251)
  line L18 (-25.2379, 13.5251) -> (-24.6817, 14.25)
  line L19 (-24.6817, 14.25) -> (-24.3321, 15.0941)
  line L20 (-24.3321, 15.0941) -> (-24.2128, 16)
  line L21 (-24.2128, 16) -> (-24.3321, 16.9059)
  line L22 (-24.3321, 16.9059) -> (-24.6817, 17.75)
  line L23 (-24.6817, 17.75) -> (-25.2379, 18.4749)
  line L24 (-25.2379, 18.4749) -> (-25.9628, 19.0311)
  line L25 (-25.9628, 19.0311) -> (-31.5054, 22.2311)
extrude "Stack bolt seat bridge (3)" add sketch "Stack bolt seat bridge (2)" along normal blind 3 bodies 4 in component "CORE | ElectronicsDeck"
ref_plane "WorkPlane22" through (0, 0, 12) normal (0, 0, 1) x (1, 0, 0) in component "CORE | ElectronicsDeck"
sketch "Stack bolt seat bridge (3)" plane through (0, 0, 12) normal (0, 0, 1) x (1, 0, 0) in component "CORE | ElectronicsDeck"
  line L0 (-35.0054, -16.1689) -> (-35.7302, -16.7251)
  line L1 (-35.7302, -16.7251) -> (-36.2865, -17.45)
  line L2 (-36.2865, -17.45) -> (-36.6361, -18.2941)
  line L3 (-36.6361, -18.2941) -> (-36.7554, -19.2)
  line L4 (-36.7554, -19.2) -> (-36.6361, -20.1059)
  line L5 (-36.6361, -20.1059) -> (-36.2865, -20.95)
  line L6 (-36.2865, -20.95) -> (-35.7302, -21.6749)
  line L7 (-35.7302, -21.6749) -> (-35.0054, -22.2311)
  line L8 (-35.0054, -22.2311) -> (-34.1612, -22.5807)
  line L9 (-34.1612, -22.5807) -> (-33.2554, -22.7)
  line L10 (-33.2554, -22.7) -> (-32.3495, -22.5807)
  line L11 (-32.3495, -22.5807) -> (-31.5054, -22.2311)
  line L12 (-31.5054, -22.2311) -> (-25.9628, -19.0311)
  line L13 (-25.9628, -19.0311) -> (-25.2379, -18.4749)
  line L14 (-25.2379, -18.4749) -> (-24.6817, -17.75)
  line L15 (-24.6817, -17.75) -> (-24.3321, -16.9059)
  line L16 (-24.3321, -16.9059) -> (-24.2128, -16)
  line L17 (-24.2128, -16) -> (-24.3321, -15.0941)
  line L18 (-24.3321, -15.0941) -> (-24.6817, -14.25)
  line L19 (-24.6817, -14.25) -> (-25.2379, -13.5251)
  line L20 (-25.2379, -13.5251) -> (-25.9628, -12.9689)
  line L21 (-25.9628, -12.9689) -> (-26.8069, -12.6193)
  line L22 (-26.8069, -12.6193) -> (-27.7128, -12.5)
  line L23 (-27.7128, -12.5) -> (-28.6187, -12.6193)
  line L24 (-28.6187, -12.6193) -> (-29.4628, -12.9689)
  line L25 (-29.4628, -12.9689) -> (-35.0054, -16.1689)
extrude "Stack bolt seat bridge (4)" add sketch "Stack bolt seat bridge (3)" along normal blind 3 bodies 4 in component "CORE | ElectronicsDeck"
ref_plane "WorkPlane23" through (0, 0, 12) normal (0, 0, 1) x (1, 0, 0) in component "CORE | ElectronicsDeck"
sketch "Stack bolt seat bridge (4)" plane through (0, 0, 12) normal (0, 0, 1) x (1, 0, 0) in component "CORE | ElectronicsDeck"
  line L0 (-3.5, -38.4) -> (-3.3807, -39.3059)
  line L1 (-3.3807, -39.3059) -> (-3.0311, -40.15)
  line L2 (-3.0311, -40.15) -> (-2.4749, -40.8749)
  line L3 (-2.4749, -40.8749) -> (-1.75, -41.4311)
  line L4 (-1.75, -41.4311) -> (-0.9059, -41.7807)
  line L5 (-0.9059, -41.7807) -> (0, -41.9)
  line L6 (0, -41.9) -> (0.9059, -41.7807)
  line L7 (0.9059, -41.7807) -> (1.75, -41.4311)
  line L8 (1.75, -41.4311) -> (2.4749, -40.8749)
  line L9 (2.4749, -40.8749) -> (3.0311, -40.15)
  line L10 (3.0311, -40.15) -> (3.3807, -39.3059)
  line L11 (3.3807, -39.3059) -> (3.5, -38.4)
  line L12 (3.5, -38.4) -> (3.5, -32)
  line L13 (3.5, -32) -> (3.3807, -31.0941)
  line L14 (3.3807, -31.0941) -> (3.0311, -30.25)
  line L15 (3.0311, -30.25) -> (2.4749, -29.5251)
  line L16 (2.4749, -29.5251) -> (1.75, -28.9689)
  line L17 (1.75, -28.9689) -> (0.9059, -28.6193)
  line L18 (0.9059, -28.6193) -> (0, -28.5)
  line L19 (0, -28.5) -> (-0.9059, -28.6193)
  line L20 (-0.9059, -28.6193) -> (-1.75, -28.9689)
  line L21 (-1.75, -28.9689) -> (-2.4749, -29.5251)
  line L22 (-2.4749, -29.5251) -> (-3.0311, -30.25)
  line L23 (-3.0311, -30.25) -> (-3.3807, -31.0941)
  line L24 (-3.3807, -31.0941) -> (-3.5, -32)
  line L25 (-3.5, -32) -> (-3.5, -38.4)
extrude "Stack bolt seat bridge (5)" add sketch "Stack bolt seat bridge (4)" along normal blind 3 bodies 4 in component "CORE | ElectronicsDeck"
ref_plane "WorkPlane24" through (0, 0, 12) normal (0, 0, 1) x (1, 0, 0) in component "CORE | ElectronicsDeck"
sketch "Stack bolt seat bridge (5)" plane through (0, 0, 12) normal (0, 0, 1) x (1, 0, 0) in component "CORE | ElectronicsDeck"
  line L0 (31.5054, -22.2311) -> (32.3495, -22.5807)
  line L1 (32.3495, -22.5807) -> (33.2554, -22.7)
  line L2 (33.2554, -22.7) -> (34.1612, -22.5807)
  line L3 (34.1612, -22.5807) -> (35.0054, -22.2311)
  line L4 (35.0054, -22.2311) -> (35.7302, -21.6749)
  line L5 (35.7302, -21.6749) -> (36.2865, -20.95)
  line L6 (36.2865, -20.95) -> (36.6361, -20.1059)
  line L7 (36.6361, -20.1059) -> (36.7554, -19.2)
  line L8 (36.7554, -19.2) -> (36.6361, -18.2941)
  line L9 (36.6361, -18.2941) -> (36.2865, -17.45)
  line L10 (36.2865, -17.45) -> (35.7302, -16.7251)
  line L11 (35.7302, -16.7251) -> (35.0054, -16.1689)
  line L12 (35.0054, -16.1689) -> (29.4628, -12.9689)
  line L13 (29.4628, -12.9689) -> (28.6187, -12.6193)
  line L14 (28.6187, -12.6193) -> (27.7128, -12.5)
  line L15 (27.7128, -12.5) -> (26.8069, -12.6193)
  line L16 (26.8069, -12.6193) -> (25.9628, -12.9689)
  line L17 (25.9628, -12.9689) -> (25.2379, -13.5251)
  line L18 (25.2379, -13.5251) -> (24.6817, -14.25)
  line L19 (24.6817, -14.25) -> (24.3321, -15.0941)
  line L20 (24.3321, -15.0941) -> (24.2128, -16)
  line L21 (24.2128, -16) -> (24.3321, -16.9059)
  line L22 (24.3321, -16.9059) -> (24.6817, -17.75)
  line L23 (24.6817, -17.75) -> (25.2379, -18.4749)
  line L24 (25.2379, -18.4749) -> (25.9628, -19.0311)
  line L25 (25.9628, -19.0311) -> (31.5054, -22.2311)
extrude "Stack bolt seat bridge (6)" add sketch "Stack bolt seat bridge (5)" along normal blind 3 bodies 4 in component "CORE | ElectronicsDeck"
ref_plane "WorkPlane25" through (0, 0, 12) normal (0, 0, 1) x (1, 0, 0) in component "CORE | ElectronicsDeck"
sketch "Core guard pillar seat" plane through (0, 0, 12) normal (0, 0, 1) x (1, 0, 0) in component "CORE | ElectronicsDeck"
  circle A0 centre (36.3731, 21) radius 4
extrude "Core guard pillar seat (1)" add sketch "Core guard pillar seat" along normal blind 3 bodies 4 in component "CORE | ElectronicsDeck"
ref_plane "WorkPlane26" through (0, 0, 12) normal (0, 0, 1) x (1, 0, 0) in component "CORE | ElectronicsDeck"
sketch "Core guard pillar seat (1)" plane through (0, 0, 12) normal (0, 0, 1) x (1, 0, 0) in component "CORE | ElectronicsDeck"
  circle A0 centre (0, 42) radius 4
extrude "Core guard pillar seat (2)" add sketch "Core guard pillar seat (1)" along normal blind 3 bodies 4 in component "CORE | ElectronicsDeck"
ref_plane "WorkPlane27" through (0, 0, 12) normal (0, 0, 1) x (1, 0, 0) in component "CORE | ElectronicsDeck"
sketch "Core guard pillar seat (2)" plane through (0, 0, 12) normal (0, 0, 1) x (1, 0, 0) in component "CORE | ElectronicsDeck"
  circle A0 centre (-36.3731, 21) radius 4
extrude "Core guard pillar seat (3)" add sketch "Core guard pillar seat (2)" along normal blind 3 bodies 4 in component "CORE | ElectronicsDeck"
ref_plane "WorkPlane28" through (0, 0, 12) normal (0, 0, 1) x (1, 0, 0) in component "CORE | ElectronicsDeck"
sketch "Core guard pillar seat (3)" plane through (0, 0, 12) normal (0, 0, 1) x (1, 0, 0) in component "CORE | ElectronicsDeck"
  circle A0 centre (-36.3731, -21) radius 4
extrude "Core guard pillar seat (4)" add sketch "Core guard pillar seat (3)" along normal blind 3 bodies 4 in component "CORE | ElectronicsDeck"
ref_plane "WorkPlane29" through (0, 0, 12) normal (0, 0, 1) x (1, 0, 0) in component "CORE | ElectronicsDeck"
sketch "Core guard pillar seat (4)" plane through (0, 0, 12) normal (0, 0, 1) x (1, 0, 0) in component "CORE | ElectronicsDeck"
  circle A0 centre (0, -42) radius 4
extrude "Core guard pillar seat (5)" add sketch "Core guard pillar seat (4)" along normal blind 3 bodies 4 in component "CORE | ElectronicsDeck"
ref_plane "WorkPlane30" through (0, 0, 12) normal (0, 0, 1) x (1, 0, 0) in component "CORE | ElectronicsDeck"
sketch "Core guard pillar seat (5)" plane through (0, 0, 12) normal (0, 0, 1) x (1, 0, 0) in component "CORE | ElectronicsDeck"
  circle A0 centre (36.3731, -21) radius 4
extrude "Core guard pillar seat (6)" add sketch "Core guard pillar seat (5)" along normal blind 3 bodies 4 in component "CORE | ElectronicsDeck"
ref_plane "WorkPlane31" through (0, 0, 12) normal (0, 0, 1) x (1, 0, 0) in component "CORE | ElectronicsDeck"
sketch "Chassis and core mounting holes" plane through (0, 0, 12) normal (0, 0, 1) x (1, 0, 0) in component "CORE | ElectronicsDeck"
  circle A0 centre (27.7128, 16) radius 1.7
  circle A1 centre (0, 32) radius 1.7
  circle A2 centre (-27.7128, 16) radius 1.7
  circle A3 centre (-27.7128, -16) radius 1.7
  circle A4 centre (0, -32) radius 1.7
  circle A5 centre (27.7128, -16) radius 1.7
  circle A6 centre (36.3731, 21) radius 1.2
  circle A7 centre (0, 42) radius 1.2
  circle A8 centre (-36.3731, 21) radius 1.2
  circle A9 centre (-36.3731, -21) radius 1.2
  circle A10 centre (0, -42) radius 1.2
  circle A11 centre (36.3731, -21) radius 1.2
extrude "Chassis and core mounting holes (1)" cut sketch "Chassis and core mounting holes" along normal blind 3 bodies 4 in component "CORE | ElectronicsDeck"
ref_plane "WorkPlane32" through (0, 0, 12) normal (0, 0, 1) x (1, 0, 0) in component "CORE | ElectronicsDeck"
sketch "PCA exact M2 through holes" plane through (0, 0, 12) normal (0, 0, 1) x (1, 0, 0) in component "CORE | ElectronicsDeck"
  circle A0 centre (-27.94, -25.525) radius 1.2
  circle A1 centre (-27.94, -6.475) radius 1.2
  circle A2 centre (27.94, -25.525) radius 1.2
  circle A3 centre (27.94, -6.475) radius 1.2
  circle A4 centre (27.94, 25.525) radius 1.2
  circle A5 centre (27.94, 6.475) radius 1.2
  circle A6 centre (-27.94, 25.525) radius 1.2
  circle A7 centre (-27.94, 6.475) radius 1.2
extrude "PCA exact M2 through holes (1)" cut sketch "PCA exact M2 through holes" along normal blind 9 bodies 4 in component "CORE | ElectronicsDeck"
ref_plane "WorkPlane1" through (0, 0, -26) normal (0, 0, 1) x (1, 0, 0) in component "CORE | LowerSpacer"
sketch "Open core spacer" plane through (0, 0, -26) normal (0, 0, 1) x (1, 0, 0) in component "CORE | LowerSpacer"
  circle A0 centre (0, 0) radius 3.5
extrude "Open core spacer (1)" add sketch "Open core spacer" along normal blind 17 separate body makes body 5 in component "CORE | LowerSpacer"
ref_plane "WorkPlane2" through (0, 0, -26) normal (0, 0, 1) x (1, 0, 0) in component "CORE | LowerSpacer"
sketch "Metal through bolt clearance" plane through (0, 0, -26) normal (0, 0, 1) x (1, 0, 0) in component "CORE | LowerSpacer"
  circle A0 centre (0, 0) radius 1.7
extrude "Metal through bolt clearance (1)" cut sketch "Metal through bolt clearance" along normal blind 17 bodies 5 in component "CORE | LowerSpacer"
ref_plane "WorkPlane1" through (0, 0, -3) normal (0, 0, 1) x (1, 0, 0) in component "CORE | UpperSpacer"
sketch "Open core spacer (2)" plane through (0, 0, -3) normal (0, 0, 1) x (1, 0, 0) in component "CORE | UpperSpacer"
  circle A0 centre (0, 0) radius 3.5
extrude "Open core spacer (1)'" add sketch "Open core spacer (2)" along normal blind 15 separate body makes body 6 in component "CORE | UpperSpacer"
ref_plane "WorkPlane2" through (0, 0, -3) normal (0, 0, 1) x (1, 0, 0) in component "CORE | UpperSpacer"
sketch "Metal through bolt clearance (2)" plane through (0, 0, -3) normal (0, 0, 1) x (1, 0, 0) in component "CORE | UpperSpacer"
  circle A0 centre (0, 0) radius 1.7
extrude "Metal through bolt clearance (1)'" cut sketch "Metal through bolt clearance (2)" along normal blind 15 bodies 6 in component "CORE | UpperSpacer"
ref_plane "WorkPlane1" through (0, 0, 15) normal (0, 0, 1) x (1, 0, 0) in component "CORE | GuardLower"
sketch "Open core spacer (3)" plane through (0, 0, 15) normal (0, 0, 1) x (1, 0, 0) in component "CORE | GuardLower"
  circle A0 centre (0, 0) radius 3.2
extrude "Open core spacer (1)''" add sketch "Open core spacer (3)" along normal blind 23 separate body makes body 7 in component "CORE | GuardLower"
ref_plane "WorkPlane2" through (0, 0, 15) normal (0, 0, 1) x (1, 0, 0) in component "CORE | GuardLower"
sketch "Metal through bolt clearance (3)" plane through (0, 0, 15) normal (0, 0, 1) x (1, 0, 0) in component "CORE | GuardLower"
  circle A0 centre (0, 0) radius 1.2
extrude "Metal through bolt clearance (1)''" cut sketch "Metal through bolt clearance (3)" along normal blind 23 bodies 7 in component "CORE | GuardLower"
ref_plane "WorkPlane1" through (0, 0, 40.4) normal (0, 0, 1) x (1, 0, 0) in component "CORE | GuardUpper"